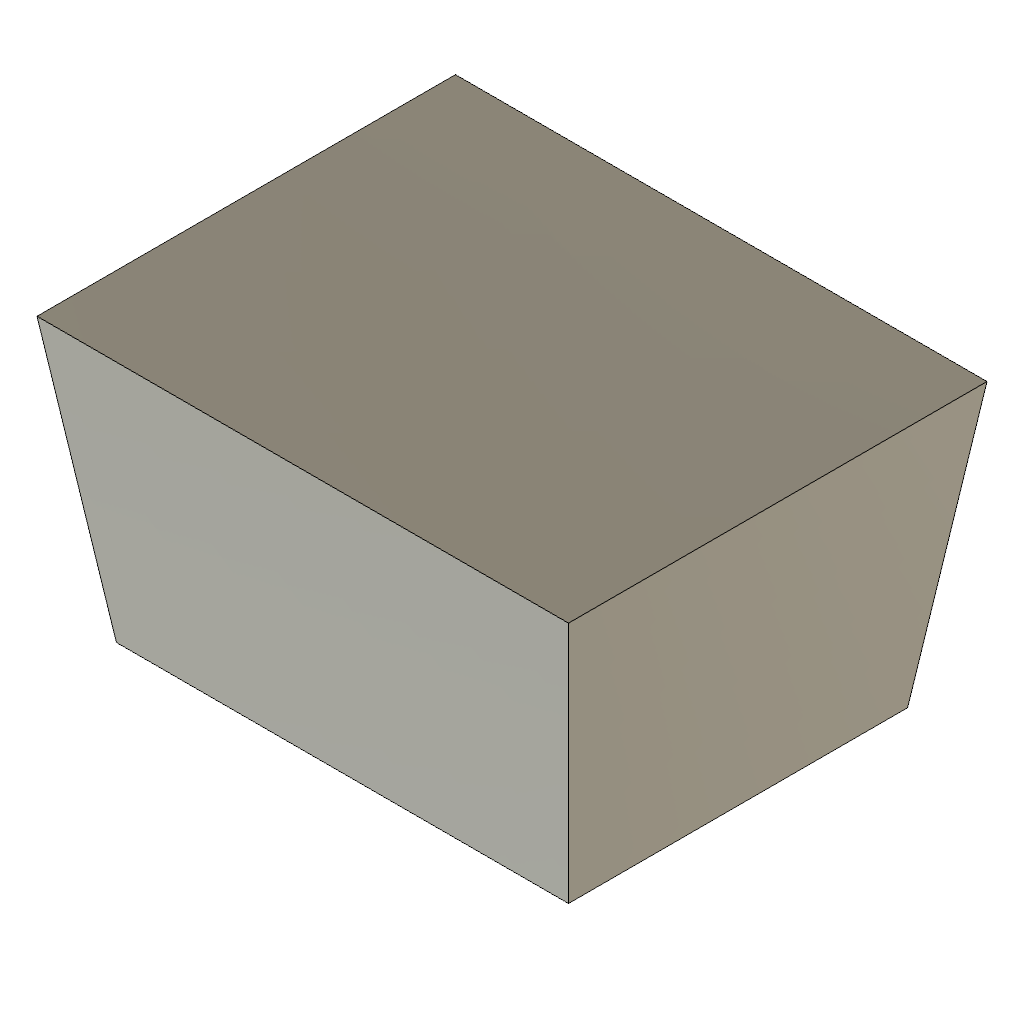
vendor_DraftSides (Autodesk Fusion 360 design; units mm, degrees)
Autodesk Fusion 360 part; units mm, degrees
sketch "Base sketch" plane through (0, 0, 0) normal (0, 0, 1) x (1, 0, 0)
  line L0 (0, 0) -> (40, 0)
  line L1 (40, 0) -> (40, 30)
  line L2 (40, 30) -> (0, 30)
  line L3 (0, 30) -> (0, 0)
extrude "Base extrude" add sketch "Base sketch" along normal blind 25
draft "Side draft" angle 8 neutral plane through (0, 0, 0) pull (0, 0, -1) 4 faces at (13.3333, 0, 8.3333) (40, 10, 16.6667) (26.6667, 30, 8.3333) (0, 20, 16.6667)
equation "height = 20.0 mm"
